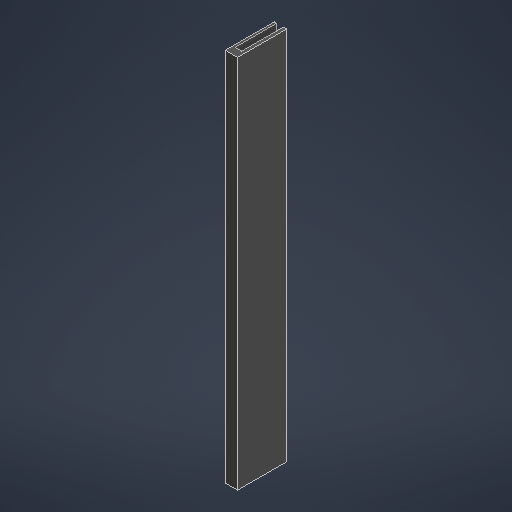
# Autodesk Inventor part: Front_Rail_Wall
Saved by Autodesk Inventor 2027.1 (Build 311270010, 270A)
## iProperties
Created: 2026-10-10
Part Number: Front_Rail_Wall
Material: 一般
Document SubType Name: Modeling
Designer: Takuya Kamada
Density: 1 g/cm^3
Appearance: 一般
Author: Takuya Kamada
Autodesk Inventor part; units mm, degrees
ref_plane "YZ Plane" through (0, 0, 0) normal (1, 0, 0) x (0, 1, 0)
sketch "スケッチ1" plane through (0, 0, 0) normal (0, 0, 1) x (1, 0, 0)
  line L0 (-1.2428, 0.7068) -> (5.2572, 0.7068) projected
  line L1 (0, -198) -> (3, -198) projected
  line L2 (3, 0) -> (3, -198) projected
  line L3 (0, 0) -> (3, 0) projected
  line L4 (0, 0) -> (0, -198) projected
  arc A0 (-1.2428, 0.7068) -> (-84.9598, 202.8177) centre (-287.0708, 0.7068) ccw projected
  arc A1 (5.2572, 0.7068) -> (-80.3637, 207.4139) centre (-287.0708, 0.7068) ccw projected
  circle A2 centre (-287.0708, 0.7068) radius 285.828 construction
  circle A3 centre (-287.0708, 0.7068) radius 292.328 construction
  line L5 (-1.2436, 0) -> (5.2564, 0)
  line L6 (-1.2436, 0) -> (5.2564, 0)
  line L7 (5.2564, 0) -> (5.2564, -198)
  line L8 (5.2564, -198) -> (-1.2436, -198)
  line L9 (-1.2436, -198) -> (-1.2436, 0)
  line L10 (-0.2428, 0.7068) -> (3.2572, 0.7068) projected
  arc A4 (-0.2428, 0.7068) -> (-84.2527, 203.5248) centre (-287.0708, 0.7068) ccw projected
  line L11 (-81.7779, 205.9997) -> (-84.2527, 203.5248) projected
  arc A5 (3.2572, 0.7068) -> (-81.7779, 205.9997) centre (-287.0708, 0.7068) ccw projected
  line L12 (-0.2428, 0.7068) -> (3.2572, 0.7068) projected
  arc A6 (-0.2428, 0.7068) -> (-84.2527, 203.5248) centre (-287.0708, 0.7068) ccw projected
  line L13 (-81.7779, 205.9997) -> (-84.2527, 203.5248) projected
  arc A7 (3.2572, 0.7068) -> (-81.7779, 205.9997) centre (-287.0708, 0.7068) ccw projected
  line L14 (0, 0) -> (3.5, 0)
  line L15 (3.5, 0) -> (3.5, -198)
  line L16 (3.5, -198) -> (0, -198)
  line L17 (0, -198) -> (0, 0)
  dimension "d0" = 3.5
  constraints: 18 end point, 4 parallel, 3 point on line, 2 coincident, 2 horizontal, 2 horizontal alignment, 2 perpendicular, 2 point on circle, 1 centre point, 6 other
  measures "d0" distance between parallel lines of L15 L17
ref_plane "作業平面1" through (-144.1568, -2.5432, 26) normal (0, 0, 1) x (0.7071, 0.7071, 0)
extrude "押し出し1" add sketch "スケッチ1" along normal up to surface (26 mm away) contours L8 L9 L5 L4 | L15 L5 L7 L8
sketch "スケッチ2" plane through (-1.2436, -198, 26) normal (0, 0, 1) x (1, 0, 0)
  line L0 (0, 0) -> (0, 198) projected
  line L1 (1.2436, 0) -> (0, 0) projected
  line L2 (1.2436, 198) -> (1.2436, 0) projected
  line L3 (0, 198) -> (1.2436, 198) projected
  line L4 (6.5, 198) -> (6.5, 0) projected
  line L5 (4.7436, 198) -> (6.5, 198) projected
  line L6 (4.7436, 0) -> (4.7436, 198) projected
  line L7 (6.5, 0) -> (4.7436, 0) projected
  line L8 (0, 198) -> (6.5, 198)
  line L9 (6.5, 198) -> (6.5, 0)
  line L10 (6.5, 0) -> (0, 0)
  line L11 (0, 0) -> (0, 198)
  point P0 (1.2436, 198)
  constraints: 8 end point, 2 parallel, 1 horizontal, 1 perpendicular
ref_plane "作業平面2" through (-143.6568, -1.0432, 22) normal (0, 0, -1) x (-0.7071, 0.7071, 0)
extrude "押し出し2" add sketch "スケッチ2" against normal up to surface (4 mm away) contours L2 L8 L6 L10
